Autodesk Fusion 360 part; units mm, degrees
(part 4 of 18)
  line L1817 (58.8847, -66.7665) -> (58.9725, -66.1793)
  line L1818 (58.7582, -67.3467) -> (58.8847, -66.7665)
  line L1819 (59.0318, -65.15) -> (59.0121, -64.5565)
  line L1820 (59.0211, -65.5875) -> (59.0318, -65.15)
  line L1821 (58.9725, -66.1793) -> (59.0211, -65.5875)
  line L1822 (19.7392, -44.7175) -> (19.9741, -45.2629)
  line L1823 (46.2951, -33.228) -> (46.8336, -33.0011)
  line L1824 (34.7525, -35.4812) -> (34.3423, -35.0519)
  line L1825 (143.904, -34.6507) -> (143.441, -34.2794)
  line L1826 (144.342, -35.0519) -> (143.904, -34.6507)
  line L1827 (142.446, -33.633) -> (141.918, -33.3606)
  line L1828 (142.954, -33.9397) -> (142.446, -33.633)
  line L1829 (143.441, -34.2794) -> (142.954, -33.9397)
  line L1830 (20.2446, -45.7915) -> (20.5495, -46.301)
  line L1831 (34.3423, -35.0519) -> (33.9045, -34.6507)
  line L1832 (46.8336, -33.0011) -> (47.3856, -32.8094)
  line L1833 (138.483, -32.5042) -> (137.889, -32.497)
  line L1834 (139.075, -32.5508) -> (138.483, -32.5042)
  line L1835 (136.707, -32.6004) -> (136.123, -32.7107)
  line L1836 (137.296, -32.5291) -> (136.707, -32.6004)
  line L1837 (137.889, -32.497) -> (137.296, -32.5291)
  line L1838 (20.8876, -46.7892) -> (21.2572, -47.2539)
  line L1839 (47.3856, -32.8094) -> (47.9488, -32.6538)
  line L1840 (47.9488, -32.6538) -> (48.5208, -32.5348)
  line L1841 (132.889, -34.1505) -> (132.417, -34.5104)
  line L1842 (133.385, -33.8228) -> (132.889, -34.1505)
  line L1843 (131.549, -35.3199) -> (131.157, -35.766)
  line L1844 (131.97, -34.9007) -> (131.549, -35.3199)
  line L1845 (132.417, -34.5104) -> (131.97, -34.9007)
  line L1846 (21.6569, -47.6931) -> (22.0847, -48.1049)
  line L1847 (37.0121, -40.8565) -> (36.9531, -40.2656)
  line L1848 (37.0318, -41.45) -> (37.0121, -40.8565)
  line L1849 (129.495, -38.8917) -> (129.344, -39.466)
  line L1850 (129.683, -38.3285) -> (129.495, -38.8917)
  line L1851 (129.159, -40.6384) -> (129.124, -41.2312)
  line L1852 (129.232, -40.0491) -> (129.159, -40.6384)
  line L1853 (129.344, -39.466) -> (129.232, -40.0491)
  line L1854 (57.9457, -36.9798) -> (58.2178, -37.4969)
  line L1855 (19.3443, -39.466) -> (19.232, -40.0491)
  line L1856 (19.1587, -40.6384) -> (19.1245, -41.2312)
  line L1857 (19.6222, -38.2215) -> (19.8482, -37.6827)
  line L1858 (19.4315, -38.7738) -> (19.6222, -38.2215)
  line L1859 (20.402, -36.6542) -> (20.7274, -36.169)
  line L1860 (20.1085, -37.1595) -> (20.402, -36.6542)
  line L1861 (19.8482, -37.6827) -> (20.1085, -37.1595)
  line L1862 (23.0175, -48.8389) -> (23.5183, -49.1579)
  line L1863 (19.232, -40.0491) -> (19.1587, -40.6384)
  line L1864 (37.0211, -41.8875) -> (37.0318, -41.45)
  line L1865 (23.2676, -33.7835) -> (23.7724, -33.4892)
  line L1866 (22.7829, -34.1099) -> (23.2676, -33.7835)
  line L1867 (24.8336, -33.0011) -> (25.3856, -32.8094)
  line L1868 (24.2951, -33.228) -> (24.8336, -33.0011)
  line L1869 (23.7724, -33.4892) -> (24.2951, -33.228)
  line L1870 (24.0392, -49.4431) -> (24.5778, -49.6931)
  line L1871 (44.3203, -34.4668) -> (44.7829, -34.1099)
  line L1872 (19.1245, -41.2312) -> (19.1297, -41.825)
  line L1873 (28.8498, -32.4331) -> (29.4301, -32.5018)
  line L1874 (28.2663, -32.402) -> (28.8498, -32.4331)
  line L1875 (30.5713, -32.7506) -> (31.1275, -32.9297)
  line L1876 (30.0047, -32.6077) -> (30.5713, -32.7506)
  line L1877 (29.4301, -32.5018) -> (30.0047, -32.6077)
  line L1878 (25.1318, -49.9069) -> (25.6987, -50.0835)
  line L1879 (57.3045, -36.0036) -> (57.6409, -36.4813)
  line L1880 (56.1207, -34.714) -> (56.5428, -35.118)
  line L1881 (34.1207, -34.714) -> (34.5428, -35.118)
  line L1882 (33.6734, -34.338) -> (34.1207, -34.714)
  line L1883 (35.3045, -36.0036) -> (35.6409, -36.4813)
  line L1884 (34.9379, -35.5485) -> (35.3045, -36.0036)
  line L1885 (34.5428, -35.118) -> (34.9379, -35.5485)
  line L1886 (26.2761, -50.2221) -> (26.8615, -50.3221)
  line L1887 (44.7829, -34.1099) -> (45.2676, -33.7835)
  line L1888 (45.2676, -33.7835) -> (45.7724, -33.4892)
  line L1889 (36.9575, -39.7077) -> (37.0514, -40.2844)
  line L1890 (36.8266, -39.1382) -> (36.9575, -39.7077)
  line L1891 (37.1268, -41.45) -> (37.1251, -41.6237)
  line L1892 (37.1079, -40.866) -> (37.1268, -41.45)
  line L1893 (37.0514, -40.2844) -> (37.1079, -40.866)
  line L1894 (27.4521, -50.3832) -> (28.0455, -50.4049)
  line L1895 (36.7582, -43.6467) -> (36.8847, -43.0665)
  line L1896 (56.9379, -35.5485) -> (57.3045, -36.0036)
  line L1897 (35.57, -46.3534) -> (35.8785, -45.846)
  line L1898 (35.5441, -46.563) -> (35.1986, -47.0342)
  line L1899 (35.8585, -46.0704) -> (35.5441, -46.563)
  line L1900 (36.1404, -45.5586) -> (35.8585, -46.0704)
  line L1901 (28.6391, -50.3873) -> (29.2302, -50.3304)
  line L1902 (36.9224, -43.3625) -> (36.7806, -43.9293)
  line L1903 (37.0274, -42.7877) -> (36.9224, -43.3625)
  line L1904 (37.0951, -42.2073) -> (37.0274, -42.7877)
  line L1905 (37.1251, -41.6237) -> (37.0951, -42.2073)
  line L1906 (34.42, -47.9049) -> (33.9903, -48.3008)
  line L1907 (34.8234, -47.4821) -> (34.42, -47.9049)
  line L1908 (35.1986, -47.0342) -> (34.8234, -47.4821)
  line L1909 (29.2302, -50.3304) -> (29.8162, -50.2345)
  line L1910 (55.6734, -34.338) -> (56.1207, -34.714)
  line L1911 (45.7724, -33.4892) -> (46.2951, -33.228)
  line L1912 (35.9457, -36.9798) -> (36.2178, -37.4969)
  line L1913 (35.6409, -36.4813) -> (35.9457, -36.9798)
  line L1914 (36.3887, -45.0297) -> (36.1404, -45.5586)
  line L1915 (36.6024, -44.4858) -> (36.3887, -45.0297)
  line L1916 (36.7806, -43.9293) -> (36.6024, -44.4858)
  line L1917 (28.0455, -50.4049) -> (28.6391, -50.3873)
  line L1918 (57.6409, -36.4813) -> (57.9457, -36.9798)
  line L1919 (31.671, -33.1443) -> (32.1995, -33.3936)
  line L1920 (31.1275, -32.9297) -> (31.671, -33.1443)
  line L1921 (36.6591, -38.5784) -> (36.8266, -39.1382)
  line L1922 (36.4559, -38.0305) -> (36.6591, -38.5784)
  line L1923 (36.2178, -37.4969) -> (36.4559, -38.0305)
  line L1924 (26.8615, -50.3221) -> (27.4521, -50.3832)
  line L1925 (24.9847, -33.0458) -> (24.4345, -33.2692)
  line L1926 (25.9488, -32.6538) -> (26.5208, -32.5348)
  line L1927 (25.3856, -32.8094) -> (25.9488, -32.6538)
  line L1928 (33.2028, -33.9917) -> (33.6734, -34.338)
  line L1929 (32.7108, -33.6764) -> (33.2028, -33.9917)
  line L1930 (32.1995, -33.3936) -> (32.7108, -33.6764)
  line L1931 (25.6987, -50.0835) -> (26.2761, -50.2221)
  line L1932 (35.1334, -35.9368) -> (34.7525, -35.4812)
  line L1933 (21.0836, -35.7057) -> (21.4688, -35.2664)
  line L1934 (20.7274, -36.169) -> (21.0836, -35.7057)
  line L1935 (27.682, -32.4086) -> (28.2663, -32.402)
  line L1936 (27.0994, -32.4529) -> (27.682, -32.4086)
  line L1937 (26.5208, -32.5348) -> (27.0994, -32.4529)
  line L1938 (24.5778, -49.6931) -> (25.1318, -49.9069)
  line L1939 (129.13, -41.825) -> (129.174, -42.4171)
  line L1940 (129.124, -41.2312) -> (129.13, -41.825)
  line L1941 (22.3203, -34.4668) -> (22.7829, -34.1099)
  line L1942 (21.8816, -34.8528) -> (22.3203, -34.4668)
  line L1943 (21.4688, -35.2664) -> (21.8816, -34.8528)
  line L1944 (23.5183, -49.1579) -> (24.0392, -49.4431)
  line L1945 (32.5813, -49.1896) -> (33.0844, -48.874)
  line L1946 (35.4833, -36.4165) -> (35.1334, -35.9368)
  line L1947 (130.795, -36.2371) -> (130.466, -36.7311)
  line L1948 (131.157, -35.766) -> (130.795, -36.2371)
  line L1949 (19.2769, -39.3373) -> (19.4315, -38.7738)
  line L1950 (19.1589, -39.9096) -> (19.2769, -39.3373)
  line L1951 (19.078, -40.4883) -> (19.1589, -39.9096)
  line L1952 (22.539, -48.4873) -> (23.0175, -48.8389)
  line L1953 (29.6626, -32.6365) -> (29.075, -32.5508)
  line L1954 (36.5935, -44.2172) -> (36.7582, -43.6467)
  line L1955 (135.548, -32.8593) -> (134.985, -33.0458)
  line L1956 (136.123, -32.7107) -> (135.548, -32.8593)
  line L1957 (129.909, -37.7791) -> (129.683, -38.3285)
  line L1958 (130.17, -37.2459) -> (129.909, -37.7791)
  line L1959 (130.466, -36.7311) -> (130.17, -37.2459)
  line L1960 (22.0847, -48.1049) -> (22.539, -48.4873)
  line L1961 (36.3914, -44.7756) -> (36.5935, -44.2172)
  line L1962 (32.0585, -49.4711) -> (32.5813, -49.1896)
  line L1963 (141.373, -33.1239) -> (140.814, -32.9237)
  line L1964 (141.918, -33.3606) -> (141.373, -33.1239)
  line L1965 (133.9, -33.5286) -> (133.385, -33.8228)
  line L1966 (134.434, -33.2692) -> (133.9, -33.5286)
  line L1967 (134.985, -33.0458) -> (134.434, -33.2692)
  line L1968 (21.2572, -47.2539) -> (21.6569, -47.6931)
  line L1969 (29.075, -32.5508) -> (28.483, -32.5042)
  line L1970 (28.483, -32.5042) -> (27.8893, -32.497)
  line L1971 (145.801, -36.9185) -> (145.483, -36.4165)
  line L1972 (146.084, -37.4403) -> (145.801, -36.9185)
  line L1973 (139.663, -32.6365) -> (139.075, -32.5508)
  line L1974 (140.243, -32.761) -> (139.663, -32.6365)
  line L1975 (140.814, -32.9237) -> (140.243, -32.761)
  line L1976 (20.5495, -46.301) -> (20.8876, -46.7892)
  line L1977 (35.8006, -36.9185) -> (35.4833, -36.4165)
  line L1978 (34.0223, -48.1465) -> (34.453, -47.7378)
  line L1979 (57.8785, -69.546) -> (58.1527, -69.0193)
  line L1980 (57.57, -70.0534) -> (57.8785, -69.546)
  line L1981 (144.753, -35.4812) -> (144.342, -35.0519)
  line L1982 (145.133, -35.9368) -> (144.753, -35.4812)
  line L1983 (145.483, -36.4165) -> (145.133, -35.9368)
  line L1984 (19.9741, -45.2629) -> (20.2446, -45.7915)
  line L1985 (36.084, -37.4403) -> (35.8006, -36.9185)
  line L1986 (26.7068, -32.6004) -> (26.1233, -32.7107)
  line L1987 (50.6391, -74.0873) -> (51.2302, -74.0304)
  line L1988 (50.0455, -74.1049) -> (50.6391, -74.0873)
  line L1989 (58.5935, -67.9172) -> (58.7582, -67.3467)
  line L1990 (58.3914, -68.4756) -> (58.5935, -67.9172)
  line L1991 (58.1527, -69.0193) -> (58.3914, -68.4756)
  line L1992 (19.541, -44.1577) -> (19.7392, -44.7175)
  line L1993 (27.2963, -32.5291) -> (26.7068, -32.6004)
  line L1994 (42.8876, -70.4892) -> (43.2572, -70.9539)
  line L1995 (42.5495, -70.001) -> (42.8876, -70.4892)
  line L1996 (52.3945, -73.7999) -> (52.9627, -73.6272)
  line L1997 (51.8162, -73.9345) -> (52.3945, -73.7999)
  line L1998 (51.2302, -74.0304) -> (51.8162, -73.9345)
  line L1999 (19.1742, -42.4171) -> (19.2578, -43.005)
  line L2000 (32.954, -33.9397) -> (32.4456, -33.633)
  line L2001 (41.3817, -67.6597) -> (41.2379, -67.0934)
  line L2002 (41.5618, -68.2156) -> (41.3817, -67.6597)
  line L2003 (44.0847, -71.8049) -> (44.539, -72.1873)
  line L2004 (43.6569, -71.3931) -> (44.0847, -71.8049)
  line L2005 (43.2572, -70.9539) -> (43.6569, -71.3931)
  line L2006 (19.0291, -41.6553) -> (19.0332, -41.2312)
  line L2007 (27.8893, -32.497) -> (27.2963, -32.5291)
  line L2008 (41.6223, -38.2215) -> (41.8482, -37.6827)
  line L2009 (47.2202, -73.7373) -> (46.672, -73.5351)
  line L2010 (47.7803, -73.9038) -> (47.2202, -73.7373)
  line L2011 (41.0612, -65.9388) -> (41.0291, -65.3553)
  line L2012 (41.1309, -66.5189) -> (41.0612, -65.9388)
  line L2013 (41.2379, -67.0934) -> (41.1309, -66.5189)
  line L2014 (19.2379, -43.3934) -> (19.1309, -42.8189)
  line L2015 (32.4456, -33.633) -> (31.9179, -33.3606)
  line L2016 (36.3321, -37.9798) -> (36.084, -37.4403)
  line L2017 (55.5358, -72.3681) -> (55.0587, -72.7054)
  line L2018 (55.9903, -72.0008) -> (55.5358, -72.3681)
  line L2019 (45.6204, -73.0267) -> (45.1214, -72.7227)
  line L2020 (46.138, -73.2979) -> (45.6204, -73.0267)
  line L2021 (46.672, -73.5351) -> (46.138, -73.2979)
  line L2022 (19.7774, -45.0587) -> (19.5618, -44.5156)
  line L2023 (36.5439, -38.5345) -> (36.3321, -37.9798)
  line L2024 (41.8482, -37.6827) -> (42.1085, -37.1595)
  line L2025 (59.1268, -65.15) -> (59.1251, -65.3237)
  line L2026 (59.1079, -64.566) -> (59.1268, -65.15)
  line L2027 (54.0441, -73.2841) -> (53.5109, -73.5231)
  line L2028 (54.5607, -73.0111) -> (54.0441, -73.2841)
  line L2029 (55.0587, -72.7054) -> (54.5607, -73.0111)
  line L2030 (20.6274, -46.589) -> (20.3113, -46.0975)
  line L2031 (42.1085, -37.1595) -> (42.402, -36.6542)
  line L2032 (36.7185, -39.1021) -> (36.5439, -38.5345)
  line L2033 (58.6591, -62.2784) -> (58.8266, -62.8382)
  line L2034 (58.4559, -61.7305) -> (58.6591, -62.2784)
  line L2035 (59.0274, -66.4877) -> (58.9224, -67.0625)
  line L2036 (59.0951, -65.9073) -> (59.0274, -66.4877)
  line L2037 (59.1251, -65.3237) -> (59.0951, -65.9073)
  line L2038 (21.7561, -47.927) -> (21.3513, -47.5056)
  line L2039 (48.5208, -32.5348) -> (49.0994, -32.4529)
  line L2040 (49.0994, -32.4529) -> (49.682, -32.4086)
  line L2041 (54.7108, -57.3764) -> (55.2028, -57.6917)
  line L2042 (54.1995, -57.0936) -> (54.7108, -57.3764)
  line L2043 (144.453, -71.4378) -> (144.856, -71.0014)
  line L2044 (58.9575, -63.4077) -> (59.0514, -63.9844)
  line L2045 (58.8266, -62.8382) -> (58.9575, -63.4077)
  line L2046 (23.1214, -49.0227) -> (22.643, -48.6871)
  line L2047 (42.402, -36.6542) -> (42.7274, -36.169)
  line L2048 (26.1233, -32.7107) -> (25.5484, -32.8593)
  line L2049 (49.0994, -56.1529) -> (49.682, -56.1086)
  line L2050 (48.5208, -56.2348) -> (49.0994, -56.1529)
  line L2051 (56.1207, -58.414) -> (56.5428, -58.818)
  line L2052 (55.6734, -58.038) -> (56.1207, -58.414)
  line L2053 (55.2028, -57.6917) -> (55.6734, -58.038)
  line L2054 (24.672, -49.8351) -> (24.138, -49.5979)
  line L2055 (49.682, -32.4086) -> (50.2663, -32.402)
  line L2056 (50.2663, -32.402) -> (50.8498, -32.4331)
  line L2057 (43.8816, -58.5528) -> (44.3203, -58.1668)
  line L2058 (43.4688, -58.9664) -> (43.8816, -58.5528)
  line L2059 (50.8498, -56.1331) -> (51.4301, -56.2018)
  line L2060 (50.2663, -56.102) -> (50.8498, -56.1331)
  line L2061 (49.682, -56.1086) -> (50.2663, -56.102)
  line L2062 (25.7803, -50.2038) -> (25.2202, -50.0373)
  line L2063 (41.1589, -39.9096) -> (41.2769, -39.3373)
  line L2064 (41.1589, -63.6096) -> (41.2769, -63.0373)
  line L2065 (41.078, -64.1883) -> (41.1589, -63.6096)
  line L2066 (45.2676, -57.4835) -> (45.7724, -57.1892)
  line L2067 (44.7829, -57.8099) -> (45.2676, -57.4835)
  line L2068 (44.3203, -58.1668) -> (44.7829, -57.8099)
  line L2069 (26.9269, -50.4266) -> (26.35, -50.3337)
  line L2070 (25.5484, -32.8593) -> (24.9847, -33.0458)
  line L2071 (121.99, -72.0008) -> (121.536, -72.3681)
  line L2072 (122.42, -71.6049) -> (121.99, -72.0008)
  line L2073 (41.6223, -61.9215) -> (41.8482, -61.3827)
  line L2074 (41.4315, -62.4738) -> (41.6223, -61.9215)
  line L2075 (41.2769, -63.0373) -> (41.4315, -62.4738)
  line L2076 (28.0926, -50.5) -> (27.5085, -50.4821)
  line L2077 (33.4411, -34.2794) -> (32.954, -33.9397)
  line L2078 (33.9045, -34.6507) -> (33.4411, -34.2794)
  line L2079 (124.922, -67.0625) -> (124.781, -67.6293)
  line L2080 (125.027, -66.4877) -> (124.922, -67.0625)
  line L2081 (120.561, -73.0111) -> (120.044, -73.2841)
  line L2082 (121.059, -72.7054) -> (120.561, -73.0111)
  line L2083 (121.536, -72.3681) -> (121.059, -72.7054)
  line L2084 (29.2581, -50.4226) -> (28.6766, -50.4801)
  line L2085 (41.2769, -39.3373) -> (41.4315, -38.7738)
  line L2086 (52.5713, -32.7506) -> (53.1275, -32.9297)
  line L2087 (124.456, -61.7305) -> (124.659, -62.2784)
  line L2088 (124.218, -61.1969) -> (124.456, -61.7305)
  line L2089 (124.389, -68.7297) -> (124.14, -69.2586)
  line L2090 (124.602, -68.1858) -> (124.389, -68.7297)
  line L2091 (124.781, -67.6293) -> (124.602, -68.1858)
  line L2092 (30.4039, -50.1957) -> (29.8346, -50.3276)
  line L2093 (24.4345, -33.2692) -> (23.9003, -33.5286)
  line L2094 (23.9003, -33.5286) -> (23.3845, -33.8228)
  line L2095 (120.711, -57.3764) -> (121.203, -57.6917)
  line L2096 (120.199, -57.0936) -> (120.711, -57.3764)
  line L2097 (124.957, -63.4077) -> (125.051, -63.9844)
  line L2098 (124.827, -62.8382) -> (124.957, -63.4077)
  line L2099 (124.659, -62.2784) -> (124.827, -62.8382)
  line L2100 (31.5109, -49.8231) -> (30.9634, -50.0273)
  line L2101 (23.3845, -33.8228) -> (22.8893, -34.1505)
  line L2102 (51.4301, -32.5018) -> (52.0047, -32.6077)
  line L2103 (115.099, -56.1529) -> (115.682, -56.1086)
  line L2104 (114.521, -56.2348) -> (115.099, -56.1529)
  line L2105 (122.121, -58.414) -> (122.543, -58.818)
  line L2106 (121.673, -58.038) -> (122.121, -58.414)
  line L2107 (121.203, -57.6917) -> (121.673, -58.038)
  line L2108 (32.5607, -49.3111) -> (32.0441, -49.5841)
  line L2109 (35.2286, -46.8393) -> (35.57, -46.3534)
  line L2110 (21.9695, -34.9007) -> (21.5489, -35.3199)
  line L2111 (111.268, -57.4835) -> (111.772, -57.1892)
  line L2112 (110.783, -57.8099) -> (111.268, -57.4835)
  line L2113 (116.85, -56.1331) -> (117.43, -56.2018)
  line L2114 (116.266, -56.102) -> (116.85, -56.1331)
  line L2115 (115.682, -56.1086) -> (116.266, -56.102)
  line L2116 (33.5358, -48.6681) -> (33.0587, -49.0054)
  line L2117 (22.417, -34.5104) -> (21.9695, -34.9007)
  line L2118 (22.8893, -34.1505) -> (22.417, -34.5104)
  line L2119 (112.295, -56.928) -> (112.834, -56.7011)
  line L2120 (111.772, -57.1892) -> (112.295, -56.928)
  line L2121 (113.949, -56.3538) -> (114.521, -56.2348)
  line L2122 (113.386, -56.5094) -> (113.949, -56.3538)
  line L2123 (112.834, -56.7011) -> (113.386, -56.5094)
  line L2124 (33.9903, -48.3008) -> (33.5358, -48.6681)
  line L2125 (52.0047, -32.6077) -> (52.5713, -32.7506)
  line L2126 (50.8498, -32.4331) -> (51.4301, -32.5018)
  line L2127 (118.005, -56.3077) -> (118.571, -56.4506)
  line L2128 (117.43, -56.2018) -> (118.005, -56.3077)
  line L2129 (119.671, -56.8443) -> (120.199, -57.0936)
  line L2130 (119.128, -56.6297) -> (119.671, -56.8443)
  line L2131 (118.571, -56.4506) -> (119.128, -56.6297)
  line L2132 (33.0587, -49.0054) -> (32.5607, -49.3111)
  line L2133 (42.7274, -36.169) -> (43.0836, -35.7057)
  line L2134 (43.0836, -35.7057) -> (43.4688, -35.2664)
  line L2135 (122.938, -59.2485) -> (123.304, -59.7036)
  line L2136 (122.543, -58.818) -> (122.938, -59.2485)
  line L2137 (123.946, -60.6798) -> (124.218, -61.1969)
  line L2138 (123.641, -60.1813) -> (123.946, -60.6798)
  line L2139 (123.304, -59.7036) -> (123.641, -60.1813)
  line L2140 (32.0441, -49.5841) -> (31.5109, -49.8231)
  line L2141 (43.4688, -35.2664) -> (43.8816, -34.8528)
  line L2142 (54.1995, -33.3936) -> (54.7108, -33.6764)
  line L2143 (125.108, -64.566) -> (125.127, -65.15)
  line L2144 (125.051, -63.9844) -> (125.108, -64.566)
  line L2145 (125.095, -65.9073) -> (125.027, -66.4877)
  line L2146 (125.125, -65.3237) -> (125.095, -65.9073)
  line L2147 (125.127, -65.15) -> (125.125, -65.3237)
  line L2148 (30.9634, -50.0273) -> (30.4039, -50.1957)
  line L2149 (43.8816, -34.8528) -> (44.3203, -34.4668)
  line L2150 (123.858, -69.7704) -> (123.544, -70.263)
  line L2151 (124.14, -69.2586) -> (123.858, -69.7704)
  line L2152 (122.823, -71.1821) -> (122.42, -71.6049)
  line L2153 (123.199, -70.7342) -> (122.823, -71.1821)
  line L2154 (123.544, -70.263) -> (123.199, -70.7342)
  line L2155 (29.8346, -50.3276) -> (29.2581, -50.4226)
  line L2156 (21.5489, -35.3199) -> (21.157, -35.766)
  line L2157 (19.1297, -41.825) -> (19.1742, -42.4171)
  line L2158 (119.511, -73.5231) -> (118.963, -73.7273)
  line L2159 (120.044, -73.2841) -> (119.511, -73.5231)
  line L2160 (85.1297, -65.525) -> (85.1742, -66.1171)
  line L2161 (85.1245, -64.9312) -> (85.1297, -65.525)
  line L2162 (85.1587, -64.3384) -> (85.1245, -64.9312)
  line L2163 (28.6766, -50.4801) -> (28.0926, -50.5)
  line L2164 (30.8143, -32.9237) -> (30.2432, -32.761)
  line L2165 (41.4315, -38.7738) -> (41.6223, -38.2215)
  line L2166 (42.1085, -60.8595) -> (42.402, -60.3542)
  line L2167 (41.8482, -61.3827) -> (42.1085, -60.8595)
  line L2168 (43.0836, -59.4057) -> (43.4688, -58.9664)
  line L2169 (42.7274, -59.869) -> (43.0836, -59.4057)
  line L2170 (42.402, -60.3542) -> (42.7274, -59.869)
  line L2171 (27.5085, -50.4821) -> (26.9269, -50.4266)
  line L2172 (21.157, -35.766) -> (20.7955, -36.2371)
  line L2173 (41.078, -40.4883) -> (41.1589, -39.9096)
  line L2174 (46.2951, -56.928) -> (46.8336, -56.7011)
  line L2175 (45.7724, -57.1892) -> (46.2951, -56.928)
  line L2176 (47.9488, -56.3538) -> (48.5208, -56.2348)
  line L2177 (47.3856, -56.5094) -> (47.9488, -56.3538)
  line L2178 (46.8336, -56.7011) -> (47.3856, -56.5094)
  line L2179 (26.35, -50.3337) -> (25.7803, -50.2038)
  line L2180 (55.2028, -33.9917) -> (55.6734, -34.338)
  line L2181 (52.0047, -56.3077) -> (52.5713, -56.4506)
  line L2182 (51.4301, -56.2018) -> (52.0047, -56.3077)
  line L2183 (53.671, -56.8443) -> (54.1995, -57.0936)
  line L2184 (53.1275, -56.6297) -> (53.671, -56.8443)
  line L2185 (52.5713, -56.4506) -> (53.1275, -56.6297)
  line L2186 (25.2202, -50.0373) -> (24.672, -49.8351)
  line L2187 (30.3945, -50.0999) -> (30.9627, -49.9272)
  line L2188 (53.671, -33.1443) -> (54.1995, -33.3936)
  line L2189 (57.3045, -59.7036) -> (57.6409, -60.1813)
  line L2190 (56.9379, -59.2485) -> (57.3045, -59.7036)
  line L2191 (58.2178, -61.1969) -> (58.4559, -61.7305)
  line L2192 (57.9457, -60.6798) -> (58.2178, -61.1969)
  line L2193 (57.6409, -60.1813) -> (57.9457, -60.6798)
  line L2194 (23.6204, -49.3267) -> (23.1214, -49.0227)
  line L2195 (36.1527, -45.3193) -> (36.3914, -44.7756)
  line L2196 (54.7108, -33.6764) -> (55.2028, -33.9917)
  line L2197 (146.594, -67.9172) -> (146.758, -67.3467)
  line L2198 (146.391, -68.4756) -> (146.594, -67.9172)
  line L2199 (59.0514, -63.9844) -> (59.1079, -64.566)
  line L2200 (146.885, -66.7665) -> (146.972, -66.1793)
  line L2201 (146.758, -67.3467) -> (146.885, -66.7665)
  line L2202 (22.1873, -48.3214) -> (21.7561, -47.927)
  line L2203 (34.8557, -47.3014) -> (35.2286, -46.8393)
  line L2204 (34.453, -47.7378) -> (34.8557, -47.3014)
  line L2205 (57.5441, -70.263) -> (57.1986, -70.7342)
  line L2206 (57.8585, -69.7704) -> (57.5441, -70.263)
  line L2207 (56.42, -71.6049) -> (55.9903, -72.0008)
  line L2208 (56.8234, -71.1821) -> (56.42, -71.6049)
  line L2209 (57.1986, -70.7342) -> (56.8234, -71.1821)
  line L2210 (20.9746, -47.059) -> (20.6274, -46.589)
  line L2211 (53.1275, -32.9297) -> (53.671, -33.1443)
  line L2212 (56.5428, -35.118) -> (56.9379, -35.5485)
  line L2213 (50.0926, -74.2) -> (49.5085, -74.1821)
  line L2214 (50.6766, -74.1801) -> (50.0926, -74.2)
  line L2215 (48.35, -74.0337) -> (47.7803, -73.9038)
  line L2216 (48.9269, -74.1266) -> (48.35, -74.0337)
  line L2217 (49.5085, -74.1821) -> (48.9269, -74.1266)
  line L2218 (20.0276, -45.5867) -> (19.7774, -45.0587)
  line L2219 (29.8162, -50.2345) -> (30.3945, -50.0999)
  line L2220 (42.6274, -70.289) -> (42.3113, -69.7975)
  line L2221 (42.9746, -70.759) -> (42.6274, -70.289)
  line L2222 (41.7774, -68.7587) -> (41.5618, -68.2156)
  line L2223 (42.0276, -69.2867) -> (41.7774, -68.7587)
  line L2224 (42.3113, -69.7975) -> (42.0276, -69.2867)
  line L2225 (19.3817, -43.9597) -> (19.2379, -43.3934)
  line L2226 (36.9725, -42.4793) -> (37.0211, -41.8875)
  line L2227 (30.2432, -32.761) -> (29.6626, -32.6365)
  line L2228 (41.541, -67.8577) -> (41.7392, -68.4175)
  line L2229 (41.3803, -67.2861) -> (41.541, -67.8577)
  line L2230 (42.2446, -69.4915) -> (42.5495, -70.001)
  line L2231 (41.9741, -68.9629) -> (42.2446, -69.4915)
  line L2232 (41.7392, -68.4175) -> (41.9741, -68.9629)
  line L2233 (19.0612, -42.2388) -> (19.0291, -41.6553)
  line L2234 (47.6987, -73.7835) -> (48.2761, -73.9221)
  line L2235 (47.1318, -73.6069) -> (47.6987, -73.7835)
  line L2236 (49.4521, -74.0832) -> (50.0455, -74.1049)
  line L2237 (48.8615, -74.0221) -> (49.4521, -74.0832)
  line L2238 (48.2761, -73.9221) -> (48.8615, -74.0221)
  line L2239 (19.0347, -41.071) -> (19.078, -40.4883)
  line L2240 (33.0844, -48.874) -> (33.5654, -48.5258)
  line L2241 (36.8847, -43.0665) -> (36.9725, -42.4793)
  line L2242 (56.0223, -71.8465) -> (56.453, -71.4378)
  line L2243 (55.5654, -72.2258) -> (56.0223, -71.8465)
  line L2244 (57.2286, -70.5393) -> (57.57, -70.0534)
  line L2245 (56.8557, -71.0014) -> (57.2286, -70.5393)
  line L2246 (56.453, -71.4378) -> (56.8557, -71.0014)
  line L2247 (19.3803, -43.5861) -> (19.541, -44.1577)
  line L2248 (31.5182, -49.7173) -> (32.0585, -49.4711)
  line L2249 (35.8785, -45.846) -> (36.1527, -45.3193)
  line L2250 (58.9531, -63.9656) -> (58.8551, -63.38)
  line L2251 (59.0121, -64.5565) -> (58.9531, -63.9656)
  line L2252 (58.7185, -62.8021) -> (58.5439, -62.2345)
  line L2253 (58.8551, -63.38) -> (58.7185, -62.8021)
  line L2254 (168.885, -43.0665) -> (168.972, -42.4793)
  line L2255 (168.972, -42.4793) -> (169.021, -41.8875)
  line L2256 (169.021, -41.8875) -> (169.032, -41.45)
  line L2257 (169.032, -41.45) -> (169.012, -40.8565)
  line L2258 (169.012, -40.8565) -> (168.953, -40.2656)
  line L2259 (168.953, -40.2656) -> (168.855, -39.68)
  line L2260 (168.855, -39.68) -> (168.719, -39.1021)
  line L2261 (168.719, -39.1021) -> (168.544, -38.5345)
  line L2262 (168.544, -38.5345) -> (168.332, -37.9798)
  line L2263 (168.332, -37.9798) -> (168.084, -37.4403)
  line L2264 (168.084, -37.4403) -> (167.801, -36.9185)
  line L2265 (167.801, -36.9185) -> (167.483, -36.4165)
  line L2266 (167.483, -36.4165) -> (167.133, -35.9368)
  line L2267 (167.133, -35.9368) -> (166.753, -35.4812)
  line L2268 (166.753, -35.4812) -> (166.342, -35.0519)
  line L2269 (166.342, -35.0519) -> (165.904, -34.6507)
  line L2270 (165.904, -34.6507) -> (165.441, -34.2794)
  line L2271 (165.441, -34.2794) -> (164.954, -33.9397)
  line L2272 (164.954, -33.9397) -> (164.446, -33.633)
  line L2273 (164.446, -33.633) -> (163.918, -33.3606)
  line L2274 (163.918, -33.3606) -> (163.373, -33.1239)
  line L2275 (163.373, -33.1239) -> (162.814, -32.9237)
  line L2276 (162.814, -32.9237) -> (162.243, -32.761)
  line L2277 (162.243, -32.761) -> (161.663, -32.6365)
  line L2278 (161.663, -32.6365) -> (161.075, -32.5508)
  line L2279 (161.075, -32.5508) -> (160.483, -32.5042)
  line L2280 (160.483, -32.5042) -> (159.889, -32.497)
  line L2281 (159.889, -32.497) -> (159.296, -32.5291)
  line L2282 (159.296, -32.5291) -> (158.707, -32.6004)
  line L2283 (158.707, -32.6004) -> (158.123, -32.7107)
  line L2284 (158.123, -32.7107) -> (157.548, -32.8593)
  line L2285 (157.548, -32.8593) -> (156.985, -33.0458)
  line L2286 (156.985, -33.0458) -> (156.434, -33.2692)
  line L2287 (156.434, -33.2692) -> (155.9, -33.5286)
  line L2288 (155.9, -33.5286) -> (155.385, -33.8228)
  line L2289 (155.385, -33.8228) -> (154.889, -34.1505)
  line L2290 (154.889, -34.1505) -> (154.417, -34.5104)
  line L2291 (154.417, -34.5104) -> (153.97, -34.9007)
  line L2292 (153.97, -34.9007) -> (153.549, -35.3199)
  line L2293 (153.549, -35.3199) -> (153.157, -35.766)
  line L2294 (153.157, -35.766) -> (152.795, -36.2371)
  line L2295 (152.795, -36.2371) -> (152.466, -36.7311)
  line L2296 (152.466, -36.7311) -> (152.17, -37.2459)
  line L2297 (152.17, -37.2459) -> (151.909, -37.7791)
  line L2298 (151.909, -37.7791) -> (151.683, -38.3285)
  line L2299 (151.683, -38.3285) -> (151.495, -38.8917)
  line L2300 (151.495, -38.8917) -> (151.344, -39.466)
  line L2301 (151.344, -39.466) -> (151.232, -40.0491)
  line L2302 (151.232, -40.0491) -> (151.159, -40.6384)
  line L2303 (151.159, -40.6384) -> (151.124, -41.2312)
  line L2304 (151.124, -41.2312) -> (151.13, -41.825)
  line L2305 (151.13, -41.825) -> (151.174, -42.4171)
  line L2306 (173.078, -40.4883) -> (173.159, -39.9096)
  line L2307 (173.159, -39.9096) -> (173.277, -39.3373)
  line L2308 (173.277, -39.3373) -> (173.432, -38.7738)
  line L2309 (173.432, -38.7738) -> (173.622, -38.2215)
  line L2310 (173.622, -38.2215) -> (173.848, -37.6827)
  line L2311 (173.848, -37.6827) -> (174.108, -37.1595)
  line L2312 (174.108, -37.1595) -> (174.402, -36.6542)
  line L2313 (174.402, -36.6542) -> (174.727, -36.169)
  line L2314 (174.727, -36.169) -> (175.084, -35.7057)
  line L2315 (175.084, -35.7057) -> (175.469, -35.2664)
  line L2316 (175.469, -35.2664) -> (175.882, -34.8528)
  line L2317 (175.882, -34.8528) -> (176.32, -34.4668)
  line L2318 (176.32, -34.4668) -> (176.783, -34.1099)
  line L2319 (176.783, -34.1099) -> (177.268, -33.7835)
  line L2320 (177.268, -33.7835) -> (177.772, -33.4892)
  line L2321 (177.772, -33.4892) -> (178.295, -33.228)
  line L2322 (178.295, -33.228) -> (178.834, -33.0011)
  line L2323 (178.834, -33.0011) -> (179.386, -32.8094)
  line L2324 (179.386, -32.8094) -> (179.949, -32.6538)
  line L2325 (179.949, -32.6538) -> (180.521, -32.5348)
  line L2326 (180.521, -32.5348) -> (181.099, -32.4529)
  line L2327 (181.099, -32.4529) -> (181.682, -32.4086)
  line L2328 (181.682, -32.4086) -> (182.266, -32.402)
  line L2329 (182.266, -32.402) -> (182.85, -32.4331)
  line L2330 (182.85, -32.4331) -> (183.43, -32.5018)
  line L2331 (183.43, -32.5018) -> (184.005, -32.6077)
  line L2332 (184.005, -32.6077) -> (184.571, -32.7506)
  line L2333 (184.571, -32.7506) -> (185.128, -32.9297)
  line L2334 (185.128, -32.9297) -> (185.671, -33.1443)
  line L2335 (185.671, -33.1443) -> (186.199, -33.3936)
  line L2336 (186.199, -33.3936) -> (186.711, -33.6764)
  line L2337 (186.711, -33.6764) -> (187.203, -33.9917)
  line L2338 (187.203, -33.9917) -> (187.673, -34.338)
  line L2339 (187.673, -34.338) -> (188.121, -34.714)
  line L2340 (188.121, -34.714) -> (188.543, -35.118)
  line L2341 (188.543, -35.118) -> (188.938, -35.5485)
  line L2342 (188.938, -35.5485) -> (189.304, -36.0036)
  line L2343 (189.304, -36.0036) -> (189.641, -36.4813)
  line L2344 (189.641, -36.4813) -> (189.946, -36.9798)
  line L2345 (189.946, -36.9798) -> (190.218, -37.4969)
  line L2346 (190.218, -37.4969) -> (190.456, -38.0305)
  line L2347 (190.456, -38.0305) -> (190.659, -38.5784)
  line L2348 (190.659, -38.5784) -> (190.827, -39.1382)
  line L2349 (190.827, -39.1382) -> (190.957, -39.7077)
  line L2350 (190.957, -39.7077) -> (191.051, -40.2844)
  line L2351 (191.051, -40.2844) -> (191.108, -40.866)
  line L2352 (191.108, -40.866) -> (191.127, -41.45)
  line L2353 (191.127, -41.45) -> (191.125, -41.6237)
  line L2354 (191.125, -41.6237) -> (191.095, -42.2073)
  line L2355 (191.095, -42.2073) -> (191.027, -42.7877)
  line L2356 (191.027, -42.7877) -> (190.922, -43.3625)
  line L2357 (190.922, -43.3625) -> (190.781, -43.9293)
  line L2358 (190.781, -43.9293) -> (190.602, -44.4858)
  line L2359 (190.602, -44.4858) -> (190.389, -45.0297)
  line L2360 (190.389, -45.0297) -> (190.14, -45.5586)
  line L2361 (190.14, -45.5586) -> (189.858, -46.0704)
  line L2362 (189.858, -46.0704) -> (189.544, -46.563)
  line L2363 (189.544, -46.563) -> (189.199, -47.0342)
  line L2364 (189.199, -47.0342) -> (188.823, -47.4821)
  line L2365 (188.823, -47.4821) -> (188.42, -47.9049)
  line L2366 (188.42, -47.9049) -> (187.99, -48.3008)
  line L2367 (187.99, -48.3008) -> (187.536, -48.6681)
  line L2368 (187.536, -48.6681) -> (187.059, -49.0054)
  line L2369 (187.059, -49.0054) -> (186.561, -49.3111)
  line L2370 (186.561, -49.3111) -> (186.044, -49.5841)
  line L2371 (186.044, -49.5841) -> (185.511, -49.8231)
  line L2372 (185.511, -49.8231) -> (184.963, -50.0273)
  line L2373 (184.963, -50.0273) -> (184.404, -50.1957)
  line L2374 (184.404, -50.1957) -> (183.835, -50.3276)
  line L2375 (183.835, -50.3276) -> (183.258, -50.4226)
  line L2376 (183.258, -50.4226) -> (182.677, -50.4801)
  line L2377 (182.677, -50.4801) -> (182.093, -50.5)
  line L2378 (182.093, -50.5) -> (181.509, -50.4821)
  line L2379 (181.509, -50.4821) -> (180.927, -50.4266)
  line L2380 (180.927, -50.4266) -> (180.35, -50.3337)
  line L2381 (180.35, -50.3337) -> (179.78, -50.2038)
  line L2382 (179.78, -50.2038) -> (179.22, -50.0373)
  line L2383 (179.22, -50.0373) -> (178.672, -49.8351)
  line L2384 (178.672, -49.8351) -> (178.138, -49.5979)
  line L2385 (178.138, -49.5979) -> (177.62, -49.3267)
  line L2386 (177.62, -49.3267) -> (177.121, -49.0227)
  line L2387 (177.121, -49.0227) -> (176.643, -48.6871)
  line L2388 (176.643, -48.6871) -> (176.187, -48.3214)
  line L2389 (176.187, -48.3214) -> (175.756, -47.927)
  line L2390 (175.756, -47.927) -> (175.351, -47.5056)
  line L2391 (175.351, -47.5056) -> (174.975, -47.059)
  line L2392 (174.975, -47.059) -> (174.627, -46.589)
  line L2393 (174.627, -46.589) -> (174.311, -46.0975)
  line L2394 (174.311, -46.0975) -> (174.028, -45.5867)
  line L2395 (174.028, -45.5867) -> (173.777, -45.0587)
  line L2396 (173.777, -45.0587) -> (173.562, -44.5156)
  line L2397 (144.022, -71.8465) -> (144.453, -71.4378)
  line L2398 (143.565, -72.2258) -> (144.022, -71.8465)
  line L2399 (143.084, -72.574) -> (143.565, -72.2258)
  line L2400 (142.581, -72.8896) -> (143.084, -72.574)
  line L2401 (142.059, -73.1711) -> (142.581, -72.8896)
  line L2402 (141.518, -73.4173) -> (142.059, -73.1711)
  line L2403 (140.963, -73.6272) -> (141.518, -73.4173)
  line L2404 (140.395, -73.7999) -> (140.963, -73.6272)
  line L2405 (139.816, -73.9345) -> (140.395, -73.7999)
  line L2406 (139.23, -74.0304) -> (139.816, -73.9345)
  line L2407 (138.639, -74.0873) -> (139.23, -74.0304)
  line L2408 (138.046, -74.1049) -> (138.639, -74.0873)
  line L2409 (137.452, -74.0832) -> (138.046, -74.1049)
  line L2410 (136.861, -74.0221) -> (137.452, -74.0832)
  line L2411 (136.276, -73.9221) -> (136.861, -74.0221)
  line L2412 (135.699, -73.7835) -> (136.276, -73.9221)
  line L2413 (135.132, -73.6069) -> (135.699, -73.7835)
  line L2414 (134.578, -73.3931) -> (135.132, -73.6069)
  line L2415 (134.039, -73.1431) -> (134.578, -73.3931)
  line L2416 (133.518, -72.8579) -> (134.039, -73.1431)
  line L2417 (133.018, -72.5389) -> (133.518, -72.8579)
  line L2418 (132.539, -72.1873) -> (133.018, -72.5389)
  line L2419 (132.085, -71.8049) -> (132.539, -72.1873)
  line L2420 (131.657, -71.3931) -> (132.085, -71.8049)
  line L2421 (131.257, -70.9539) -> (131.657, -71.3931)
  line L2422 (130.888, -70.4892) -> (131.257, -70.9539)
  line L2423 (130.55, -70.001) -> (130.888, -70.4892)
  line L2424 (130.245, -69.4915) -> (130.55, -70.001)
  line L2425 (129.974, -68.9629) -> (130.245, -69.4915)
  line L2426 (129.739, -68.4175) -> (129.974, -68.9629)
  line L2427 (129.541, -67.8577) -> (129.739, -68.4175)
  line L2428 (129.38, -67.2861) -> (129.541, -67.8577)
  line L2429 (129.258, -66.705) -> (129.38, -67.2861)
  line L2430 (129.174, -66.1171) -> (129.258, -66.705)
  line L2431 (129.035, -64.771) -> (129.078, -64.1883)
  line L2432 (129.033, -64.9312) -> (129.035, -64.771)
  line L2433 (129.029, -65.3553) -> (129.033, -64.9312)
  line L2434 (129.061, -65.9388) -> (129.029, -65.3553)
  line L2435 (129.131, -66.5189) -> (129.061, -65.9388)
  line L2436 (129.238, -67.0934) -> (129.131, -66.5189)
  line L2437 (129.382, -67.6597) -> (129.238, -67.0934)
  line L2438 (129.562, -68.2156) -> (129.382, -67.6597)
  line L2439 (129.777, -68.7587) -> (129.562, -68.2156)
  line L2440 (130.028, -69.2867) -> (129.777, -68.7587)
  line L2441 (130.311, -69.7975) -> (130.028, -69.2867)
  line L2442 (130.627, -70.289) -> (130.311, -69.7975)
  line L2443 (130.975, -70.759) -> (130.627, -70.289)
  line L2444 (131.351, -71.2056) -> (130.975, -70.759)
  line L2445 (131.756, -71.627) -> (131.351, -71.2056)
  line L2446 (132.187, -72.0214) -> (131.756, -71.627)
  line L2447 (132.643, -72.3871) -> (132.187, -72.0214)
  line L2448 (134.138, -73.2979) -> (133.62, -73.0267)
  line L2449 (133.62, -73.0267) -> (133.121, -72.7227)
  line L2450 (134.672, -73.5351) -> (134.138, -73.2979)
  line L2451 (133.121, -72.7227) -> (132.643, -72.3871)
  line L2452 (115.889, -56.197) -> (115.296, -56.2291)
  line L2453 (109.882, -153.353) -> (110.32, -152.967)
  line L2454 (107.909, -61.4791) -> (107.683, -62.0285)
  line L2455 (111.518, -72.8579) -> (112.039, -73.1431)
  line L2456 (110.32, -152.967) -> (110.783, -152.61)
  line L2457 (129.432, -62.4738) -> (129.622, -61.9215)
  line L2458 (114.276, -73.9221) -> (114.861, -74.0221)
  line L2459 (118.243, -56.461) -> (117.663, -56.3365)
  line L2460 (131.882, -58.5528) -> (132.32, -58.1668)
  line L2461 (138.093, -74.2) -> (137.509, -74.1821)
  line L2462 (114.861, -74.0221) -> (115.452, -74.0832)
  line L2463 (142.199, -57.0936) -> (142.711, -57.3764)
  line L2464 (143.536, -72.3681) -> (143.059, -72.7054)
  line L2465 (133.772, -57.1892) -> (134.295, -56.928)
  line L2466 (145.544, -70.263) -> (145.199, -70.7342)
  line L2467 (110.085, -71.8049) -> (110.539, -72.1873)
  line L2468 (108.028, -69.2867) -> (107.777, -68.7587)
  line L2469 (142.044, -73.2841) -> (141.511, -73.5231)
  line L2470 (116.483, -56.2042) -> (115.889, -56.197)
  line L2471 (124.594, -67.9172) -> (124.758, -67.3467)
  line L2472 (145.304, -59.7036) -> (145.641, -60.1813)
  line L2473 (174.17, -155.746) -> (173.909, -156.279)
  line L2474 (111.385, -57.5228) -> (110.889, -57.8505)
  line L2475 (118.005, -151.108) -> (118.571, -151.251)
  line L2476 (123.801, -60.6185) -> (123.483, -60.1165)
  line L2477 (110.889, -57.8505) -> (110.417, -58.2104)
  line L2478 (107.078, -158.988) -> (107.159, -158.41)
  line L2479 (113.22, -73.7373) -> (112.672, -73.5351)
  line L2480 (121.565, -72.2258) -> (122.022, -71.8465)
  line L2481 (174.795, -154.737) -> (174.466, -155.231)
  line L2482 (122.342, -58.7519) -> (121.904, -58.3507)
  line L2483 (134.834, -56.7011) -> (135.386, -56.5094)
  line L2484 (119.128, -151.43) -> (119.671, -151.644)
  line L2485 (107.541, -67.8577) -> (107.739, -68.4175)
  line L2486 (109.97, -58.6007) -> (109.549, -59.0199)
  line L2487 (124.827, -157.638) -> (124.957, -158.208)
  line L2488 (107.258, -66.705) -> (107.38, -67.2861)
  line L2489 (112.434, -56.9692) -> (111.9, -57.2286)
  line L2490 (109.756, -71.627) -> (109.351, -71.2056)
  line L2491 (124.953, -63.9656) -> (124.855, -63.38)
  line L2492 (117.43, -151.002) -> (118.005, -151.108)
  line L2493 (118.963, -73.7273) -> (118.404, -73.8957)
  line L2494 (143.99, -72.0008) -> (143.536, -72.3681)
  line L2495 (115.296, -56.2291) -> (114.707, -56.3004)
  line L2496 (107.159, -158.41) -> (107.277, -157.837)
  line L2497 (134.295, -56.928) -> (134.834, -56.7011)
  line L2498 (108.402, -155.154) -> (108.727, -154.669)
  line L2499 (110.783, -152.61) -> (111.268, -152.284)
  line L2500 (145.858, -69.7704) -> (145.544, -70.263)
  line L2501 (118.814, -56.6237) -> (118.243, -56.461)
  line L2502 (129.078, -64.1883) -> (129.159, -63.6096)
  line L2503 (173.13, -160.325) -> (173.174, -160.917)
  line L2504 (120.199, -151.894) -> (120.711, -152.176)
  line L2505 (111.121, -72.7227) -> (110.643, -72.3871)
  line L2506 (146.14, -69.2586) -> (145.858, -69.7704)
  line L2507 (121.673, -152.838) -> (122.121, -153.214)
  line L2508 (125.032, -65.15) -> (125.012, -64.5565)
  line L2509 (136.521, -56.2348) -> (137.099, -56.1529)
  line L2510 (107.777, -68.7587) -> (107.562, -68.2156)
  line L2511 (111.018, -72.5389) -> (111.518, -72.8579)
  line L2512 (122.938, -154.049) -> (123.304, -154.504)
  line L2513 (146.456, -61.7305) -> (146.659, -62.2784)
  line L2514 (146.922, -67.0625) -> (146.781, -67.6293)
  line L2515 (147.125, -65.3237) -> (147.095, -65.9073)
  line L2516 (124.218, -155.997) -> (124.456, -156.531)
  line L2517 (119.373, -56.8239) -> (118.814, -56.6237)
  line L2518 (112.834, -151.501) -> (113.386, -151.309)
  line L2519 (108.627, -70.289) -> (108.311, -69.7975)
  line L2520 (113.949, -151.154) -> (114.521, -151.035)
  line L2521 (111.62, -73.0267) -> (111.121, -72.7227)
  line L2522 (113.699, -73.7835) -> (114.276, -73.9221)
  line L2523 (135.949, -56.3538) -> (136.521, -56.2348)
  line L2524 (110.187, -72.0214) -> (109.756, -71.627)
  line L2525 (112.039, -73.1431) -> (112.578, -73.3931)
  line L2526 (117.663, -56.3365) -> (117.075, -56.2508)
  line L2527 (123.641, -154.981) -> (123.946, -155.48)
  line L2528 (125.021, -65.5875) -> (125.032, -65.15)
  line L2529 (137.509, -74.1821) -> (136.927, -74.1266)
  line L2530 (140.963, -73.7273) -> (140.404, -73.8957)
  line L2531 (112.578, -73.3931) -> (113.132, -73.6069)
  line L2532 (124.758, -67.3467) -> (124.885, -66.7665)
  line L2533 (140.571, -56.4506) -> (141.128, -56.6297)
  line L2534 (132.783, -57.8099) -> (133.268, -57.4835)
  line L2535 (131.469, -58.9664) -> (131.882, -58.5528)
  line L2536 (117.075, -56.2508) -> (116.483, -56.2042)
  line L2537 (144.121, -58.414) -> (144.543, -58.818)
  line L2538 (122.856, -71.0014) -> (123.229, -70.5393)
  line L2539 (143.673, -58.038) -> (144.121, -58.414)
  line L2540 (139.258, -74.1226) -> (138.677, -74.1801)
  line L2541 (135.22, -73.7373) -> (134.672, -73.5351)
  line L2542 (130.108, -60.8595) -> (130.402, -60.3542)
  line L2543 (107.432, -157.274) -> (107.622, -156.722)
  line L2544 (145.199, -70.7342) -> (144.823, -71.1821)
  line L2545 (124.544, -62.2345) -> (124.332, -61.6798)
  line L2546 (124.719, -62.8021) -> (124.544, -62.2345)
  line L2547 (108.795, -59.9371) -> (108.466, -60.4311)
  line L2548 (141.128, -56.6297) -> (141.671, -56.8443)
  line L2549 (133.268, -57.4835) -> (133.772, -57.1892)
  line L2550 (124.972, -66.1793) -> (125.021, -65.5875)
  line L2551 (107.033, -64.9312) -> (107.035, -64.771)
  line L2552 (139.43, -56.2018) -> (140.005, -56.3077)
  line L2553 (146.218, -61.1969) -> (146.456, -61.7305)
  line L2554 (146.389, -68.7297) -> (146.14, -69.2586)
  line L2555 (124.391, -68.4756) -> (124.594, -67.9172)
  line L2556 (108.975, -70.759) -> (108.627, -70.289)
  line L2557 (135.386, -56.5094) -> (135.949, -56.3538)
  line L2558 (121.904, -58.3507) -> (121.441, -57.9794)
  line L2559 (107.38, -67.2861) -> (107.541, -67.8577)
  line L2560 (107.035, -64.771) -> (107.078, -64.1883)
  line L2561 (107.495, -62.5917) -> (107.344, -63.166)
  line L2562 (115.099, -150.953) -> (115.682, -150.909)
  line L2563 (130.402, -60.3542) -> (130.727, -59.869)
  line L2564 (147.108, -64.566) -> (147.127, -65.15)
  line L2565 (140.404, -73.8957) -> (139.835, -74.0276)
  line L2566 (108.466, -60.4311) -> (108.17, -60.9459)
  line L2567 (108.727, -154.669) -> (109.084, -154.206)
  line L2568 (113.78, -73.9038) -> (113.22, -73.7373)
  line L2569 (124.885, -66.7665) -> (124.972, -66.1793)
  line L2570 (173.683, -156.829) -> (173.495, -157.392)
  line L2571 (124.957, -158.208) -> (125.051, -158.784)
  line L2572 (119.671, -151.644) -> (120.199, -151.894)
  line L2573 (107.848, -156.183) -> (108.108, -155.66)
  line L2574 (109.657, -71.3931) -> (110.085, -71.8049)
  line L2575 (117.816, -73.9345) -> (118.395, -73.7999)
  line L2576 (175.549, -153.82) -> (175.157, -154.266)
  line L2577 (124.332, -61.6798) -> (124.084, -61.1403)
  line L2578 (113.386, -151.309) -> (113.949, -151.154)
  line L2579 (108.311, -69.7975) -> (108.028, -69.2867)
  line L2580 (110.539, -72.1873) -> (111.018, -72.5389)
  line L2581 (177.385, -152.323) -> (176.889, -152.651)
  line L2582 (132.32, -58.1668) -> (132.783, -57.8099)
  line L2583 (115.682, -150.909) -> (116.266, -150.902)
  line L2584 (107.739, -68.4175) -> (107.974, -68.9629)
  line L2585 (108.245, -69.4915) -> (108.55, -70.001)
  line L2586 (114.521, -151.035) -> (115.099, -150.953)
  line L2587 (107.382, -67.6597) -> (107.238, -67.0934)
  line L2588 (123.946, -155.48) -> (124.218, -155.997)
  line L2589 (136.35, -74.0337) -> (135.78, -73.9038)
  line L2590 (123.879, -69.546) -> (124.153, -69.0193)
  line L2591 (173.124, -159.731) -> (173.13, -160.325)
  line L2592 (124.659, -157.078) -> (124.827, -157.638)
  line L2593 (116.046, -74.1049) -> (116.639, -74.0873)
  line L2594 (129.277, -63.0373) -> (129.432, -62.4738)
  line L2595 (115.452, -74.0832) -> (116.046, -74.1049)
  line L2596 (129.622, -61.9215) -> (129.848, -61.3827)
  line L2597 (147.027, -66.4877) -> (146.922, -67.0625)
  line L2598 (109.157, -59.466) -> (108.795, -59.9371)
  line L2599 (113.548, -56.5593) -> (112.985, -56.7458)
  line L2600 (111.268, -152.284) -> (111.772, -151.989)
  line L2601 (147.127, -65.15) -> (147.125, -65.3237)
  line L2602 (124.855, -63.38) -> (124.719, -62.8021)
  line L2603 (112.985, -56.7458) -> (112.434, -56.9692)
  line L2604 (110.417, -58.2104) -> (109.97, -58.6007)
  line L2605 (116.266, -150.902) -> (116.85, -150.933)
  line L2606 (144.938, -59.2485) -> (145.304, -59.7036)
  line L2607 (130.727, -59.869) -> (131.084, -59.4057)
  line L2608 (107.029, -65.3553) -> (107.033, -64.9312)
  line L2609 (115.509, -74.1821) -> (114.927, -74.1266)
  line L2610 (122.022, -71.8465) -> (122.453, -71.4378)
  line L2611 (147.095, -65.9073) -> (147.027, -66.4877)
  line L2612 (124.456, -156.531) -> (124.659, -157.078)
  line L2613 (146.827, -62.8382) -> (146.957, -63.4077)
  line L2614 (117.835, -74.0276) -> (117.258, -74.1226)
  line L2615 (143.203, -57.6917) -> (143.673, -58.038)
  line L2616 (123.57, -70.0534) -> (123.879, -69.546)
  line L2617 (135.78, -73.9038) -> (135.22, -73.7373)
  line L2618 (107.174, -66.1171) -> (107.258, -66.705)
  line L2619 (108.55, -70.001) -> (108.888, -70.4892)
  line L2620 (176.889, -152.651) -> (176.417, -153.01)
  line L2621 (116.093, -74.2) -> (115.509, -74.1821)
  line L2622 (119.518, -73.4173) -> (120.059, -73.1711)
  line L2623 (173.344, -157.966) -> (173.232, -158.549)
  line L2624 (122.453, -71.4378) -> (122.856, -71.0014)
  line L2625 (138.85, -56.1331) -> (139.43, -56.2018)
  line L2626 (124.084, -61.1403) -> (123.801, -60.6185)
  line L2627 (173.495, -157.392) -> (173.344, -157.966)
  line L2628 (118.404, -73.8957) -> (117.835, -74.0276)
  line L2629 (145.946, -60.6798) -> (146.218, -61.1969)
  line L2630 (114.927, -74.1266) -> (114.35, -74.0337)
  line L2631 (111.9, -57.2286) -> (111.385, -57.5228)
  line L2632 (121.084, -72.574) -> (121.565, -72.2258)
  line L2633 (173.909, -156.279) -> (173.683, -156.829)
  line L2634 (109.549, -59.0199) -> (109.157, -59.466)
  line L2635 (146.602, -68.1858) -> (146.389, -68.7297)
  line L2636 (109.257, -70.9539) -> (109.657, -71.3931)
  line L2637 (107.974, -68.9629) -> (108.245, -69.4915)
  line L2638 (111.772, -151.989) -> (112.295, -151.728)
  line L2639 (107.131, -66.5189) -> (107.061, -65.9388)
  line L2640 (118.963, -73.6272) -> (119.518, -73.4173)
  line L2641 (177.9, -152.029) -> (177.385, -152.323)
  line L2642 (114.707, -56.3004) -> (114.123, -56.4107)
  line L2643 (120.446, -57.333) -> (119.918, -57.0606)
  line L2644 (107.562, -68.2156) -> (107.382, -67.6597)
  line L2645 (109.084, -154.206) -> (109.469, -153.766)
  line L2646 (107.683, -62.0285) -> (107.495, -62.5917)
  line L2647 (141.671, -56.8443) -> (142.199, -57.0936)
  line L2648 (116.639, -74.0873) -> (117.23, -74.0304)
  line L2649 (142.711, -57.3764) -> (143.203, -57.6917)
  line L2650 (121.203, -152.492) -> (121.673, -152.838)
  line L2651 (109.351, -71.2056) -> (108.975, -70.759)
  line L2652 (141.511, -73.5231) -> (140.963, -73.7273)
  line L2653 (176.417, -153.01) -> (175.97, -153.401)
  line L2654 (173.232, -158.549) -> (173.159, -159.138)
  line L2655 (140.005, -56.3077) -> (140.571, -56.4506)
  line L2656 (117.23, -74.0304) -> (117.816, -73.9345)
  line L2657 (107.124, -64.9312) -> (107.13, -65.525)
  line L2658 (118.571, -151.251) -> (119.128, -151.43)
  line L2659 (125.012, -64.5565) -> (124.953, -63.9656)
  line L2660 (121.441, -57.9794) -> (120.954, -57.6397)
  line L2661 (120.059, -73.1711) -> (120.581, -72.8896)
  line L2662 (175.97, -153.401) -> (175.549, -153.82)
  line L2663 (107.277, -157.837) -> (107.432, -157.274)
  line L2664 (129.159, -63.6096) -> (129.277, -63.0373)
  line L2665 (112.138, -73.2979) -> (111.62, -73.0267)
  line L2666 (113.132, -73.6069) -> (113.699, -73.7835)
  line L2667 (136.927, -74.1266) -> (136.35, -74.0337)
  line L2668 (117.258, -74.1226) -> (116.677, -74.1801)
  line L2669 (145.641, -60.1813) -> (145.946, -60.6798)
  line L2670 (143.059, -72.7054) -> (142.561, -73.0111)
  line L2671 (124.153, -69.0193) -> (124.391, -68.4756)
  line L2672 (122.543, -153.618) -> (122.938, -154.049)
  line L2673 (173.159, -159.138) -> (173.124, -159.731)
  line L2674 (120.954, -57.6397) -> (120.446, -57.333)
  line L2675 (112.672, -73.5351) -> (112.138, -73.2979)
  line L2676 (107.622, -156.722) -> (107.848, -156.183)
  line L2677 (120.711, -152.176) -> (121.203, -152.492)
  line L2678 (110.643, -72.3871) -> (110.187, -72.0214)
  line L2679 (139.835, -74.0276) -> (139.258, -74.1226)
  line L2680 (122.753, -59.1812) -> (122.342, -58.7519)
  line L2681 (144.543, -58.818) -> (144.938, -59.2485)
  line L2682 (116.85, -150.933) -> (117.43, -151.002)
  line L2683 (146.957, -63.4077) -> (147.051, -63.9844)
  line L2684 (123.133, -59.6368) -> (122.753, -59.1812)
  line L2685 (112.295, -151.728) -> (112.834, -151.501)
  line L2686 (137.682, -56.1086) -> (138.266, -56.102)
  line L2687 (114.123, -56.4107) -> (113.548, -56.5593)
  line L2688 (107.13, -65.525) -> (107.174, -66.1171)
  line L2689 (107.061, -65.9388) -> (107.029, -65.3553)
  line L2690 (131.084, -59.4057) -> (131.469, -58.9664)
  line L2691 (146.659, -62.2784) -> (146.827, -62.8382)
  line L2692 (175.157, -154.266) -> (174.795, -154.737)
  line L2693 (108.17, -60.9459) -> (107.909, -61.4791)
  line L2694 (147.051, -63.9844) -> (147.108, -64.566)
  line L2695 (174.466, -155.231) -> (174.17, -155.746)
  line L2696 (107.238, -67.0934) -> (107.131, -66.5189)
  line L2697 (108.108, -155.66) -> (108.402, -155.154)
  line L2698 (138.677, -74.1801) -> (138.093, -74.2)
  line L2699 (107.232, -63.7491) -> (107.159, -64.3384)
  line L2700 (122.121, -153.214) -> (122.543, -153.618)
  line L2701 (142.561, -73.0111) -> (142.044, -73.2841)
  line L2702 (123.229, -70.5393) -> (123.57, -70.0534)
  line L2703 (108.888, -70.4892) -> (109.257, -70.9539)
  line L2704 (119.918, -57.0606) -> (119.373, -56.8239)
  line L2705 (144.823, -71.1821) -> (144.42, -71.6049)
  line L2706 (107.159, -64.3384) -> (107.124, -64.9312)
  line L2707 (129.848, -61.3827) -> (130.108, -60.8595)
  line L2708 (118.395, -73.7999) -> (118.963, -73.6272)
  line L2709 (146.781, -67.6293) -> (146.602, -68.1858)
  line L2710 (116.677, -74.1801) -> (116.093, -74.2)
  line L2711 (120.581, -72.8896) -> (121.084, -72.574)
  line L2712 (114.35, -74.0337) -> (113.78, -73.9038)
  line L2713 (123.483, -60.1165) -> (123.133, -59.6368)
  line L2714 (137.099, -56.1529) -> (137.682, -56.1086)
  line L2715 (138.266, -56.102) -> (138.85, -56.1331)